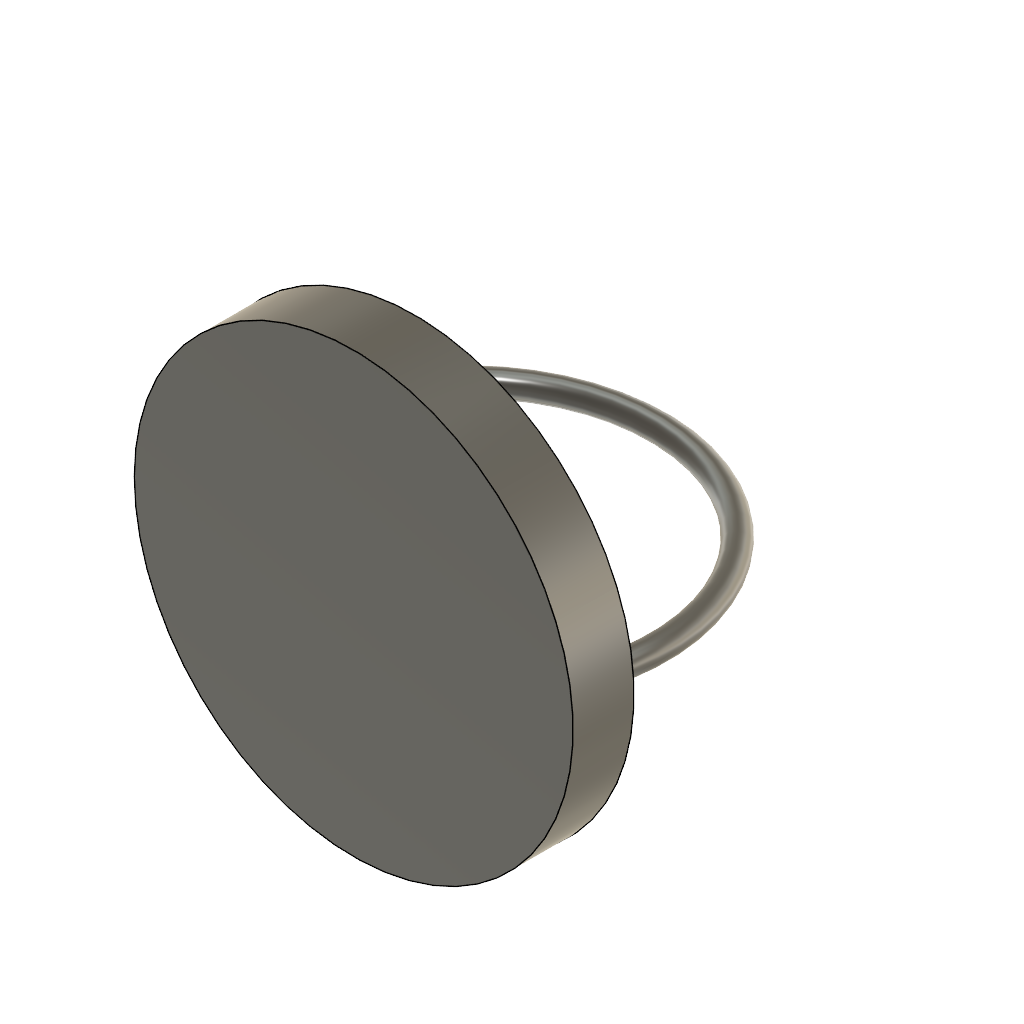
Proyecto_Integrador_Ensamblaje_S17 (Autodesk Fusion 360 archive; units mm, degrees)
design "P3_tapa_proyecto_integrador"
part number: 2026-10-22-12-01-22-288
Autodesk Fusion 360 part; units mm, degrees
sketch "Boceto1" plane through (0, 0, 0) normal (0, 1, 0) x (1, 0, 0)
  circle A0 centre (0, 0) radius 18
  dimension "d1" = 36
  constraint coincident A0.centre origin
  measures "d1" diameter of A0
extrude "Extruir1" add sketch "Boceto1" along normal blind 5
sketch "Boceto2" plane through (0, 0, 0) normal (0, -1, 0) x (1, 0, 0)
  circle A0 centre (0, 0) radius 18
  circle A1 centre (0, 0) radius 13.8
  dimension "d4" = 27.6
  constraint concentric A0 A1
  measures "d4" diameter of A1
extrude "Extruir2" add sketch "Boceto2" against normal blind 0.15 contours A1
sketch "Boceto3" plane through (0, 0, 0) normal (0, 0, 1) x (1, 0, 0)
  arc A0 (15, 5) -> (-15, 5) centre (0, 9.375) ccw
pipe "Tubería1" add diameter 1.953 path "Boceto3" along A0

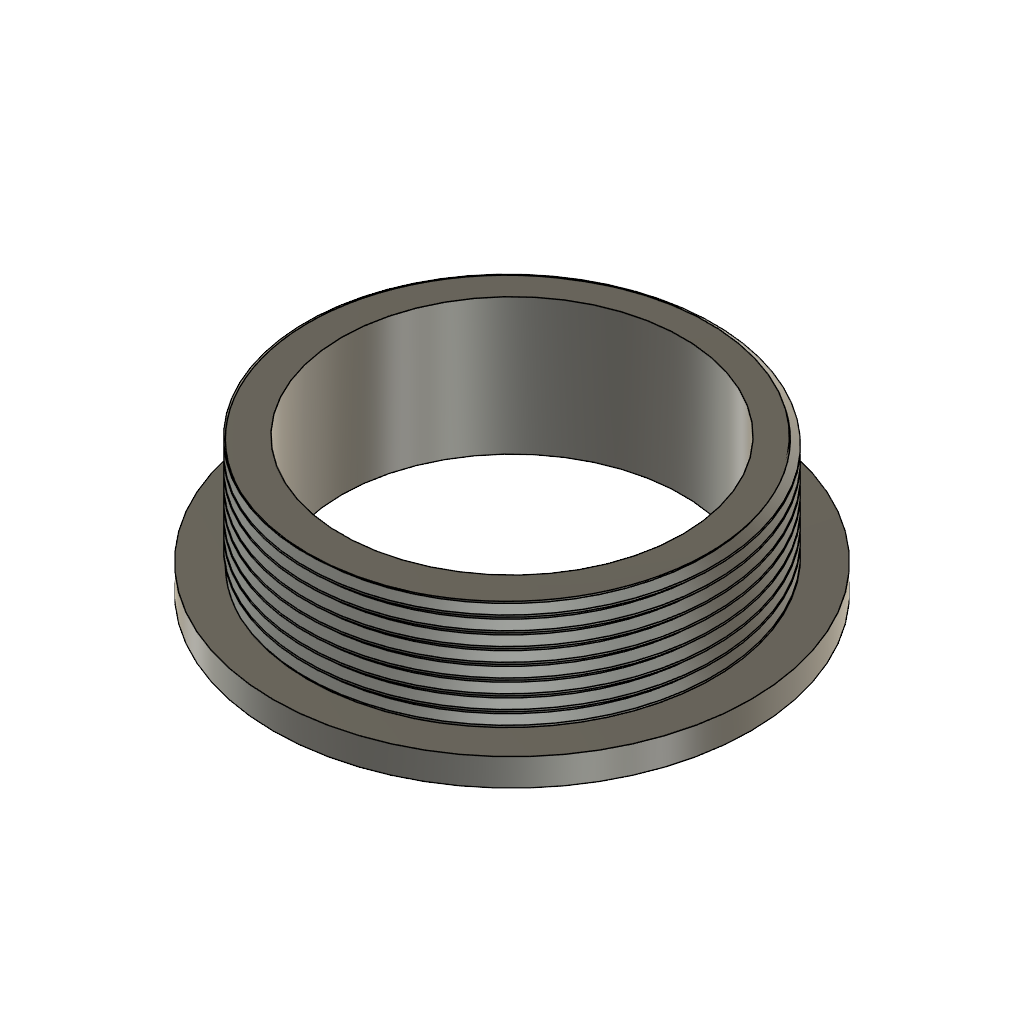
design "P1_Proyecto integrador"
part number: 2026-10-04-21-39-52-740
Autodesk Fusion 360 part; units mm, degrees
sketch "Boceto1" plane through (0, 0, 0) normal (0, 0, 1) x (1, 0, 0)
  circle A0 centre (-0.2638, 0) radius 35
  circle A1 centre (-0.2638, 0) radius 25
  dimension "d1" = 70
  dimension "d2" = 50
  constraint concentric A0 A1
  measures "d1" diameter of A0
  measures "d2" diameter of A1
extrude "Extruir1" add sketch "Boceto1" along normal blind 4
sketch "Boceto2" plane through (0, 0, 4) normal (0, 0, 1) x (-1, 0, 0)
  circle A0 centre (0.2638, 0) radius 25
  circle A1 centre (0.2638, 0) radius 35
  circle A2 centre (0.2638, 0) radius 30
  circle A3 centre (0.2638, 0) radius 25
  dimension "d5" = 60
  dimension "d6" = 50
  constraint concentric A0 A2
  constraint concentric A2 A3
  measures "d5" diameter of A2
  measures "d6" diameter of A3
extrude "Extruir2" add sketch "Boceto2" along normal blind 16 contours A2
thread "Rosca1" "ISO Metric profile 60.0 M60x2 M60x2 6g" major diameter 59.822 minor diameter 57.5239 pitch 2 angle 60 modelled right hand crest width 0.2789 on face at (-30.2265, 1.4954, 14.6667) crest through (-30.1748, 0, 3.5)
sketch "Boceto3" plane through (0, 0, 4) normal (0, 0, 1) x (-1, 0, 0)
  arc A0 (12.952, 27.0865) -> (-12.4245, 27.0865) centre (0.2638, 0) ccw
  spline S0 degree 3 poles (12.952, 27.0865) (15.3085, 25.9292) (17.5023, 24.4667) (21.4396, 21.0126) (23.168, 19.0386) (26.7437, 13.6643) (28.2292, 10.0813) (29.7329, 2.5735) (29.7468, -1.2771) (28.2981, -8.7388) (26.8598, -12.2802) (22.7175, -18.5865) (20.0621, -21.2966) (16.9607, -23.4193) knots -6.129419 -6.129419 -6.129419 -6.129419 -5.342405 -5.342405 -4.559184 -4.559184 -3.407083 -3.407083 -2.263184 -2.263184 -1.127489 -1.127489 0 0 0 0
  arc A1 (-16.4331, -23.4193) -> (16.9607, -23.4193) centre (0.2638, 0) ccw
  spline S1 degree 3 poles (-16.4331, -23.4193) (-18.5265, -21.9865) (-20.4211, -20.283) (-23.7251, -16.4157) (-25.1174, -14.2666) (-27.8397, -8.5344) (-28.7805, -4.8193) (-29.1916, 2.7905) (-28.6475, 6.6125) (-26.1203, 13.8614) (-24.1517, 17.215) (-19.0246, 23.0036) (-15.9077, 25.3758) (-12.4245, 27.0865) knots -6.134444 -6.134444 -6.134444 -6.134444 -5.372862 -5.372862 -4.607481 -4.607481 -3.467925 -3.467925 -2.320159 -2.320159 -1.164184 -1.164184 0 0 0 0
  circle A2 centre (0.2638, 0) radius 35

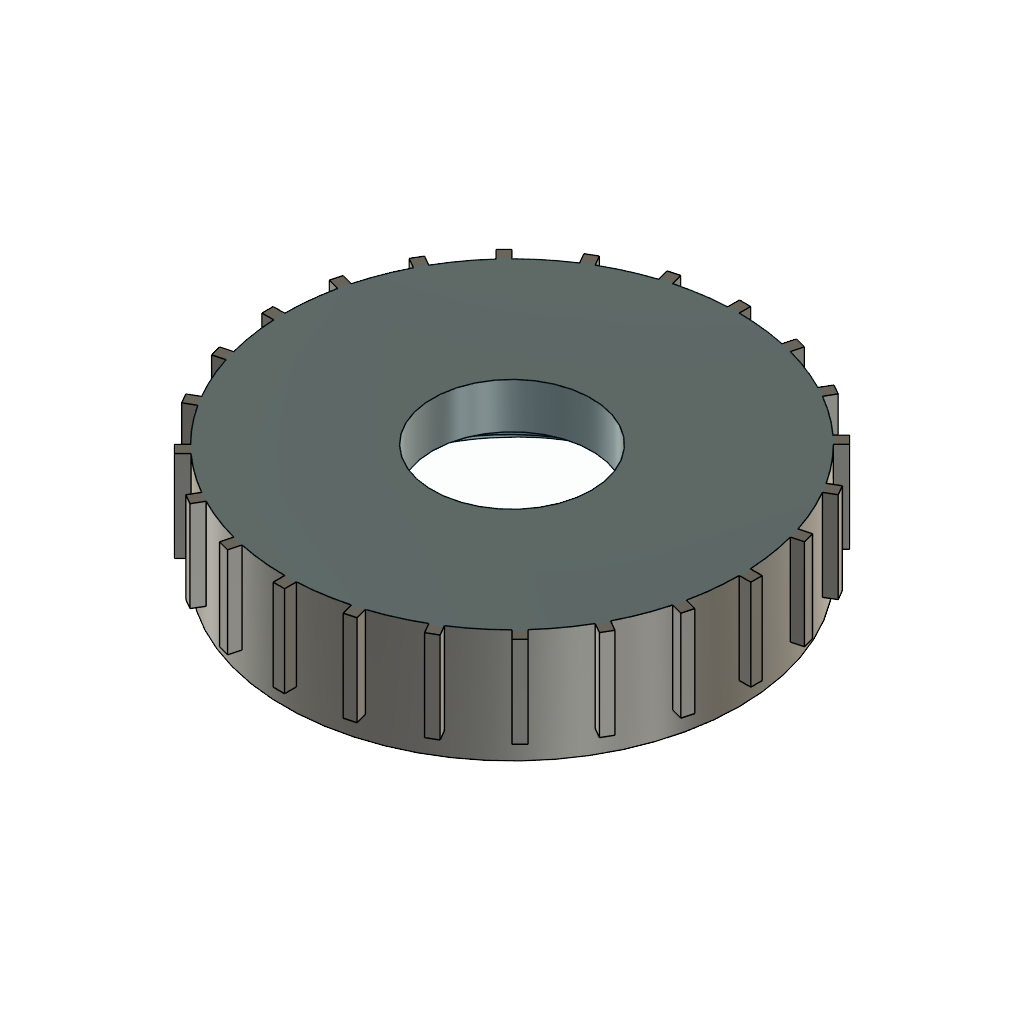
design "P2_Proyecto_Integrador"
part number: 2026-10-07-11-36-52-378
Autodesk Fusion 360 part; units mm, degrees
sketch "Boceto1" plane through (0, 0, 0) normal (0, 0, 1) x (1, 0, 0)
  circle A0 centre (0, 0) radius 40
  dimension "d1" = 80
  constraint coincident A0.centre origin
  measures "d1" diameter of A0
extrude "Extruir1" add sketch "Boceto1" along normal blind 20
sketch "Boceto2" plane through (0, 0, 20) normal (0, 0, 1) x (-1, 0, 0)
  circle A0 centre (0, 0) radius 40
  circle A1 centre (0, 0) radius 14
  dimension "d4" = 28
  constraint coincident A0.centre A1.centre
  measures "d4" diameter of A1
hole "Agujero1" at (0, 0, 20) direction (0, 0, -1) diameter 28 depth 20 tip angle 118
sketch "Boceto3" plane through (0, 0, 0) normal (0, 0, 1) x (1, 0, 0)
  circle A0 centre (0, 0) radius 30
  dimension "d8" = 60
  constraint coincident A0.centre origin
  measures "d8" diameter of A0
extrude "Extruir2" cut sketch "Boceto3" along normal blind 12
thread "Rosca1" "ISO Metric profile 60.0 M60x2 M60x2 6H" major diameter 60.2623 minor diameter 58.0224 pitch 2 angle 60 modelled right hand crest width 0.5401 on face at (29.9627, -1.4954, 8) from (0, 0, 0) to (0, 0, 12) crest through (29.0112, 0, 0.5)
sketch "Boceto4" plane through (0, 0, 20) normal (0, 0, 1) x (-1, 0, 0)
  circle A0 centre (0, 0) radius 14
  circle A1 centre (0, 0) radius 40
sketch "Boceto5" plane through (0, 0, 0) normal (0, 1, 0) x (1, 0, 0)
  line L0 (39.0352, -20) -> (42.0352, -20)
  line L1 (42.0352, -20) -> (42.0352, -4)
  line L2 (42.0352, -4) -> (39.0352, -4)
  line L3 (39.0352, -4) -> (39.0352, -20)
  dimension "d13" = 16
  dimension "d14" = 3
  constraint horizontal L0
  constraint vertical L1
  constraint horizontal L2
  constraint vertical L3
  measures "d13" distance of L0.start L2.end
  measures "d14" distance of L0.start L0.end
extrude "Extruir3" add sketch "Boceto5" along normal blind 2
pattern_circular "Patrón C1" count 3 over 360 about axis through (0, 0, 1.75) along (0, 0, 1) of "Extruir3"
pattern_circular "Patrón C2" count 24 over 360 about axis through (0, 0, 1.75) along (0, 0, 1) of "Extruir3"
